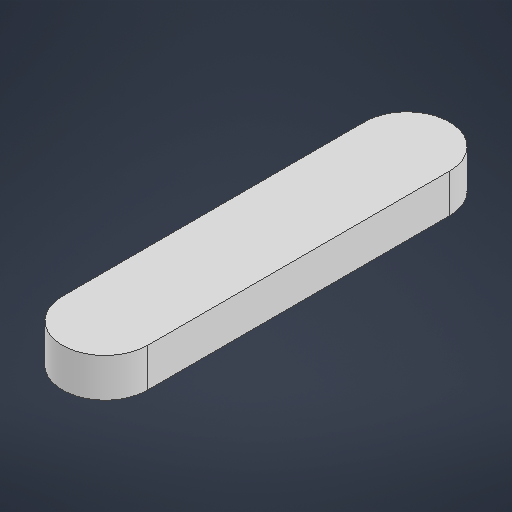
# Autodesk Inventor part: bras50
Saved by Autodesk Inventor 2026 (Build 300175000, 175)
## iProperties
Created: 2026-10-28
Part Number: bras50
Material: Generic
Document SubType Name: Modeling
Designer: alexp
Density: 1 g/cm^3
Appearance: Default
Author: alexp
Autodesk Inventor part; units mm, degrees
ref_plane "YZ Plane" through (0, 0, 0) normal (1, 0, 0) x (0, 1, 0)
ref_plane "XZ Plane" through (0, 0, 0) normal (0, 1, 0) x (-1, 0, 0)
ref_plane "XY Plane" through (0, 0, 0) normal (0, 0, 1) x (1, 0, 0)
sketch "Sketch1" plane through (0, 0, 0) normal (0, 1, 0) x (-1, 0, 0)
  line L0 (6.968, 33.2519) -> (6.968, -5.7481) construction
  line L1 (12.468, 33.2519) -> (12.468, -5.7481)
  line L2 (1.468, -5.7481) -> (1.468, 33.2519)
  arc A0 (12.468, 33.2519) -> (1.468, 33.2519) centre (6.968, 33.2519) ccw
  arc A1 (1.468, -5.7481) -> (12.468, -5.7481) centre (6.968, -5.7481) ccw
  point P0 (0, 0)
  point P1 (6.968, 13.7519)
  point P2 (6.968, -11.2481)
  point P3 (6.968, 38.7519)
  dimension "d0" = 11
  dimension "d1" = 50
  constraints: 8 end point, 6 point on circle, 4 tangent, 2 centre point, 1 midpoint, 1 parallel, 1 vertical
  measures "d0" distance between parallel lines of L1 L2
  measures "d1" distance of point (6.968, -11.248) point (6.968, 38.752)
extrude "Extrusion1" add sketch "Sketch1" along normal blind 5
body "Solid1"
